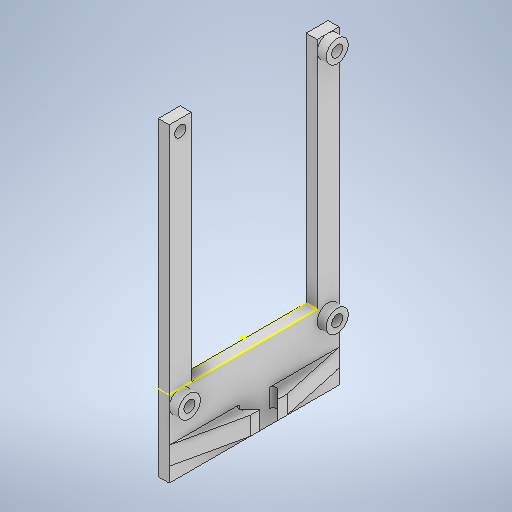
# Autodesk Inventor part: Support_pcb
Saved by Autodesk Inventor 2025 (Build 290162000, 162)
## iProperties
Created: 2026-10-27
Part Number: Support_pcb
Material: Generic
Document SubType Name: Modeling
Designer: diego
Density: 1 g/cm^3
Appearance: Default
Author: diego
Autodesk Inventor part; units mm, degrees
ref_plane "YZ Plane" through (0, 0, 0) normal (1, 0, 0) x (0, 1, 0)
ref_plane "XZ Plane" through (0, 0, 0) normal (0, 1, 0) x (-1, 0, 0)
ref_plane "XY Plane" through (0, 0, 0) normal (0, 0, 1) x (1, 0, 0)
sketch "Sketch1" plane through (0, 0, 0) normal (1, 0, 0) x (0, 1, 0)
  line L0 (-35, 23.25) -> (35, 23.25)
  line L1 (35, 23.25) -> (35, -23.25)
  line L2 (35, -23.25) -> (-35, -23.25)
  line L3 (-35, -23.25) -> (-35, 23.25)
  line L4 (-35, 23.25) -> (35, -23.25) construction
  line L5 (35, 23.25) -> (-35, -23.25) construction
  point P0 (0, 0)
  dimension "d0" = 70
  dimension "d1" = 46.5
  constraints: 12 end point, 2 midpoint, 2 parallel, 1 horizontal, 1 perpendicular
  measures "d0" distance of L1.end L2.end
  measures "d1" distance of L0.end L1.end
extrude "Extrusion1" add sketch "Sketch1" along normal blind 3
sketch "Sketch2" plane through (3, 0, 0) normal (1, 0, 0) x (0, 0, -1)
  line L0 (-20.25, -32) -> (20.25, -32)
  line L1 (20.25, -32) -> (20.25, 32)
  line L2 (20.25, 32) -> (-20.25, 32)
  line L3 (-20.25, 32) -> (-20.25, -32)
  line L4 (-20.25, -32) -> (20.25, 32) construction
  line L5 (20.25, -32) -> (-20.25, 32) construction
  circle A0 centre (-20.25, 32) radius 1.5
  circle A1 centre (20.25, 32) radius 1.5
  circle A2 centre (20.25, -32) radius 1.5
  circle A3 centre (-20.25, -32) radius 1.5
  point P0 (0, 0)
  dimension "d4" = 40.5
  dimension "d5" = 64
  dimension "d6" = 3
  dimension "d7" = 3
  dimension "d8" = 3
  dimension "d9" = 3
  constraints: 12 end point, 4 centre point, 4 coincident, 2 midpoint, 2 parallel, 1 horizontal, 1 perpendicular
  measures "d4" distance of L2.end L1.end
  measures "d5" distance of L1.end L0.end
  measures "d6" diameter of A0
  measures "d7" diameter of A1
  measures "d8" diameter of A2
  measures "d9" diameter of A3
extrude "Extrusion2" cut sketch "Sketch2" against normal blind 3 contours L3 A3 L0 | L0 A3 L3 | A2 L1 L0 | L0 L1 A2 | A0 L2 L3 | L3 L2 A0 | A1 L2 L1 | L1 L2 A1
sketch "Sketch3" plane through (3, 0, 0) normal (1, 0, 0) x (0, 0, -1)
  circle A0 centre (20.25, -32) radius 1.5 projected
  circle A1 centre (20.25, 32) radius 1.5 projected
  circle A2 centre (-20.25, -32) radius 1.5 projected
  circle A3 centre (-20.25, 32) radius 1.5 projected
  line L0 (23.25, -35) -> (23.25, 35) projected
  line L1 (23.25, 35) -> (-23.25, 35) projected
  line L2 (-23.25, 35) -> (-23.25, -35) projected
  line L3 (-23.25, -35) -> (23.25, -35) projected
  circle A4 centre (-20.25, 32) radius 3
  circle A5 centre (20.25, 32) radius 3
  circle A6 centre (-20.25, -32) radius 3
  circle A7 centre (20.25, -32) radius 3
  point P0 (0, 0)
  dimension "d12" = 1.5
  dimension "d13" = 1.5
  dimension "d14" = 1.5
  dimension "d15" = 1.5
  constraints: 4 centre point
  measures "d12" radial gap between concentric circles of A3 A4
  measures "d13" radial gap between concentric circles of A1 A5
  measures "d14" radial gap between concentric circles of A2 A6
  measures "d15" radial gap between concentric circles of A0 A7
extrude "Extrusion3" add sketch "Sketch3" along normal blind 2.5 contours A7 | A5 | A6 | A4
sketch "Sketch4" plane through (3, -35, -23.25) normal (1, 0, 0) x (0, 0, -1)
  line L0 (0, 0) -> (0, 3) projected
  line L1 (0, 70) -> (-3, 70) projected
  arc A0 (0, 67) -> (-3, 70) centre (-3, 67) ccw projected
  line L2 (-3, 70) -> (-43.5, 70) projected
  arc A1 (-46.5, 67) -> (-43.5, 70) centre (-43.5, 67) ccw projected
  line L3 (-43.5, 70) -> (-46.5, 70) projected
  line L4 (-46.5, 70) -> (-46.5, 67) projected
  line L5 (-46.5, 0) -> (-43.5, 0) projected
  arc A2 (-46.5, 3) -> (-43.5, 0) centre (-43.5, 3) ccw projected
  line L6 (-43.5, 0) -> (-3, 0) projected
  arc A3 (0, 3) -> (-3, 0) centre (-3, 3) ccw projected
  line L7 (-3, 0) -> (0, 0) projected
  line L8 (-40.5, 70) -> (-40.5, 0)
  circle A4 centre (-43.5, 67) radius 3 projected
  line L9 (-6, 70) -> (-6, 0)
  circle A5 centre (-3, 67) radius 3 projected
  line L10 (0, 3) -> (0, 67) projected
  arc A6 (-3, 70) -> (0, 67) centre (-3, 67) ccw projected
  line L11 (-46.5, 67) -> (-46.5, 3) projected
  arc A7 (-43.5, 0) -> (-46.5, 3) centre (-43.5, 3) ccw projected
  arc A8 (-3, 0) -> (0, 3) centre (-3, 3) ccw projected
  line L12 (-46.5, 3) -> (-46.5, 0) projected
  line L13 (0, 67) -> (0, 70) projected
  arc A9 (-43.5, 70) -> (-46.5, 67) centre (-43.5, 67) ccw projected
  line L14 (0, 6) -> (-46.5, 6)
  circle A10 centre (-3, 3) radius 3 projected
  point P0 (-23.25, 35)
  point P1 (-40.5, 6)
  point P2 (-6, 6)
  constraints: 6 end point, 6 point on line, 3 perpendicular, 2 vertical, 2 vertical alignment, 1 tangent
extrude "Extrusion4" cut sketch "Sketch4" against normal through all contours L14 L8 L2 L9
sketch "Sketch5" plane through (0, -35, -23.25) normal (0, -1, 0) x (1, 0, 0)
  line L0 (0, 46.5) -> (0, 0) projected
  line L1 (0, 0) -> (3, 0) projected
  line L2 (3, 3) -> (3, 0) projected
  line L3 (3, 43.5) -> (3, 3) projected
  line L4 (3, 46.5) -> (3, 43.5) projected
  line L5 (0, 46.5) -> (3, 46.5) projected
  point P0 (0, 23.25)
extrude "Extrusion5" add sketch "Sketch5" along normal blind 15
sketch "Sketch6" plane through (0, -50, -23.25) normal (0, -1, 0) x (1, 0, 0)
  line L0 (0, 46.5) -> (0, 0) projected
  line L1 (0, 0) -> (3, 0) projected
  line L2 (3, 0) -> (3, 46.5) projected
  line L3 (3, 46.5) -> (0, 46.5) projected
  line L4 (1.5, 46.5) -> (16.5, 23.25)
  line L5 (16.5, 23.25) -> (1.5, 0)
  line L6 (1.5, 0) -> (-13.5, 23.25)
  line L7 (-13.5, 23.25) -> (1.5, 46.5)
  line L8 (-13.5, 23.25) -> (16.5, 23.25)
  point P0 (0, 23.25)
  point P1 (1.5, 23.25)
  dimension "d24" = 15
  constraints: 10 end point, 3 midpoint, 2 parallel, 1 horizontal
  measures "d24" distance of L4.end point (1.5, 23.25)
extrude "Extrusion6" add sketch "Sketch6" against normal blind 3 contours L7 L4 L2 L8 L0 | L0 L8 L7 | L8 L2 L5 L6 L0 | L0 L6 L8 | L4 L8 L2 | L8 L5 L2
sketch "Sketch7" plane through (5.5, 32, 20.25) normal (1, 0, 0) x (0, 0, -1)
  circle A0 centre (0, 0) radius 3 projected
  circle A1 centre (0, 0) radius 1.5 projected
  point P0 (20.25, -32)
extrude "Extrusion7" cut sketch "Sketch7" against normal up to surface (2.5 mm away)
sketch "Sketch8" plane through (3, -32, 20.25) normal (1, 0, 0) x (0, 0, -1)
  circle A0 centre (0, 64) radius 1.5 projected
  line L0 (3, 67) -> (-3, 67) projected
  line L1 (-3, 67) -> (-3, 0) projected
  circle A1 centre (0, 0) radius 3 projected
  line L2 (-3, 0) -> (-3, -18) projected
  line L3 (-0.675, -18) -> (-3, -18) projected
  line L4 (-0.675, -18) -> (-0.675, -15) projected
  line L5 (-0.675, -15) -> (41.175, -15) projected
  line L6 (41.175, -15) -> (41.175, -18) projected
  line L7 (43.5, -18) -> (41.175, -18) projected
  line L8 (43.5, 0) -> (43.5, -18) projected
  circle A2 centre (40.5, 0) radius 3 projected
  line L9 (43.5, 0) -> (43.5, 64) projected
  arc A3 (37.5, 64) -> (43.5, 64) centre (40.5, 64) ccw projected
  line L10 (37.5, 64) -> (37.5, 3) projected
  line L11 (37.5, 3) -> (3, 3) projected
  line L12 (3, 3) -> (3, 67) projected
  line L13 (0, -3) -> (40.5, -3)
  circle A4 centre (0, 0) radius 3 projected
  line L14 (41.175, -18) -> (20.25, -18) projected
  line L15 (20.25, -18) -> (20.25, -3)
  line L16 (-0.675, -18) -> (20.25, -18) projected
  line L17 (12.25, -3) -> (15.25, -3)
  line L18 (15.25, -3) -> (15.25, -18)
  line L19 (15.25, -18) -> (12.25, -18)
  line L20 (12.25, -18) -> (12.25, -3)
  line L21 (25.25, -3) -> (25.25, -18)
  line L22 (28.25, -18) -> (28.25, -3)
  point P0 (20.25, 32)
  point P1 (28.25, -18)
  point P2 (28.25, -3)
  point P3 (25.25, -3)
  point P4 (25.25, -18)
  point P5 (15.25, -3)
  dimension "d27" = 3
  dimension "d28" = 5
  constraints: 16 end point, 4 symmetric about line, 2 parallel, 2 point on circle, 2 point on line, 2 tangent, 1 horizontal, 1 midpoint, 1 perpendicular
  measures "d27" distance between parallel lines of L18 L20
  measures "d28" distance between parallel lines of L21 L15
extrude "Extrusion8" add sketch "Sketch8" along normal blind 10 and the other way blind 13 contours L13 L18 L5 L20 | L5 L18 L16 L20 | L13 L22 L5 L21 | L5 L22 L14 L21
sketch "Sketch9" plane through (3, -47, -8) normal (0, 0, -1) x (-1, 0, 0)
  line L0 (-8.3387, 0) -> (-8.3387, -3) projected
  line L1 (0, 0) -> (-8.3387, 0) projected
  line L2 (0, 12) -> (0, 0) projected
  line L3 (-10, 12) -> (0, 12) projected
  line L4 (-10, -3) -> (-10, 12) projected
  line L5 (-8.3387, -3) -> (-10, -3) projected
  line L6 (-10, 0) -> (0, 0) projected
  line L7 (-10, 0) -> (0, 12)
  line L8 (3, 0) -> (3, 12) projected
  line L9 (11.3387, 0) -> (3, 0) projected
  line L10 (11.3387, -3) -> (11.3387, 0) projected
  line L11 (13, -3) -> (11.3387, -3) projected
  line L12 (13, 12) -> (13, -3) projected
  line L13 (3, 12) -> (13, 12) projected
  line L14 (13, 0) -> (3, 12)
  line L15 (3, 0) -> (13, 0) projected
  point P0 (3, 47)
  constraints: 4 end point, 2 point on line
extrude "Extrusion9" cut sketch "Sketch9" along normal through all both and the other way through all contours L4 L3 L7 | L13 L12 L14
sketch "Sketch10" plane through (3, -29, 17.25) normal (0, 1, 0) x (1, 0, 0)
  line L0 (-3, 0) -> (-3, 34.5) projected
  line L1 (0, 0) -> (-3, 0) projected
  line L2 (0, 34.5) -> (0, 0) projected
  line L3 (0, 34.5) -> (-3, 34.5) projected
  line L4 (0, 0) -> (-3, 0) projected
  line L5 (-3, 0) -> (-3, -6) projected
  line L6 (-3, -6) -> (0, -6) projected
  line L7 (0, 0) -> (0, -6) projected
  point P0 (-3, 17.25)
sketch "Sketch11" plane through (0, -47, -23.25) normal (0, 1, 0) x (1, 0, 0)
  line L0 (3, -15.25) -> (13, -15.25) projected
  line L1 (3, -18.25) -> (3, -15.25) projected
  line L2 (13, -18.25) -> (3, -18.25) projected
  line L3 (13, -17.825) -> (13, -18.25) projected
  line L4 (13, -15.25) -> (13, -17.825) projected
  line L5 (13, -31.25) -> (3, -31.25) projected
  line L6 (13, -28.675) -> (13, -31.25) projected
  line L7 (13, -28.25) -> (13, -28.675) projected
  line L8 (3, -28.25) -> (13, -28.25) projected
  line L9 (3, -31.25) -> (3, -28.25) projected
  line L10 (-10, -28.25) -> (0, -28.25) projected
  line L11 (-10, -28.675) -> (-10, -28.25) projected
  line L12 (-10, -31.25) -> (-10, -28.675) projected
  line L13 (0, -31.25) -> (-10, -31.25) projected
  line L14 (0, -28.25) -> (0, -31.25) projected
  line L15 (-10, -15.25) -> (0, -15.25) projected
  line L16 (-10, -17.825) -> (-10, -15.25) projected
  line L17 (-10, -18.25) -> (-10, -17.825) projected
  line L18 (0, -18.25) -> (-10, -18.25) projected
  line L19 (0, -15.25) -> (0, -18.25) projected
  point P0 (0, -23.25)
extrude "Extrusion10" cut sketch "Sketch11" along normal blind 14.7625
sketch "Sketch12" plane through (0, -50, -23.25) normal (0, -1, 0) x (1, 0, 0)
  line L0 (-8.3387, 15.25) -> (0, 2.325) projected
  line L1 (0, 2.325) -> (0, 0) projected
  line L2 (0, 0) -> (3, 0) projected
  line L3 (3, 0) -> (3, 2.325) projected
  line L4 (3, 2.325) -> (11.3387, 15.25) projected
  line L5 (11.3387, 15.25) -> (13, 15.25) projected
  line L6 (13, 17.825) -> (13, 15.25) projected
  line L7 (13, 17.825) -> (16.5, 23.25) projected
  line L8 (16.5, 23.25) -> (13, 28.675) projected
  line L9 (13, 31.25) -> (13, 28.675) projected
  line L10 (13, 31.25) -> (11.3387, 31.25) projected
  line L11 (11.3387, 31.25) -> (3, 44.175) projected
  line L12 (3, 44.175) -> (3, 46.5) projected
  line L13 (3, 46.5) -> (0, 46.5) projected
  line L14 (0, 46.5) -> (0, 44.175) projected
  line L15 (0, 44.175) -> (-8.3387, 31.25) projected
  line L16 (-8.3387, 31.25) -> (-10, 31.25) projected
  line L17 (-10, 28.675) -> (-10, 31.25) projected
  line L18 (-10, 28.675) -> (-13.5, 23.25) projected
  line L19 (-13.5, 23.25) -> (-10, 17.825) projected
  line L20 (-10, 15.25) -> (-10, 17.825) projected
  line L21 (-10, 15.25) -> (-8.3387, 15.25) projected
  line L22 (3, 44.175) -> (3, 2.325) projected
  line L23 (3, 0) -> (3, 2.325) projected
  line L24 (3, 6) -> (3, 0) projected
  line L25 (3, 0) -> (3, 6) projected
  line L26 (3, 6) -> (3, 40.5) projected
  line L27 (3, 40.5) -> (3, 46.5) projected
  line L28 (3, 46.5) -> (3, 40.5) projected
  line L29 (3, 44.175) -> (3, 46.5) projected
  line L30 (3, 42) -> (3, 45) projected
  line L31 (3, 6) -> (3, 40.5) projected
  line L32 (0, 2.325) -> (0, 44.175) projected
  line L33 (0, 46.5) -> (0, 44.175) projected
  line L34 (0, 40.5) -> (0, 46.5) projected
  line L35 (0, 40.5) -> (0, 6) projected
  line L36 (0, 0) -> (0, 6) projected
  line L37 (0, 2.325) -> (0, 0) projected
  line L38 (0, 42) -> (0, 45) projected
  line L39 (0, 42) -> (0, 45) projected
  line L40 (0, 1.5) -> (0, 4.5) projected
  line L41 (0, 1.5) -> (0, 4.5) projected
  point P0 (0, 23.25)
extrude "Extrusion11" cut sketch "Sketch12" against normal blind 10 contours L21 L20 L19 L18 L17 L16 L15 L32 L0 | L22 L11 L10 L9 L8 L7 L6 L5 L4
sketch "Sketch13" plane through (3, -32, -20.25) normal (1, 0, 0) x (0, 0, -1)
  circle A0 centre (-40.5, 64) radius 1.5 projected
  line L0 (3, -18) -> (-43.5, -18) projected
  line L1 (3, 0) -> (3, -18) projected
  circle A1 centre (0, 0) radius 3 projected
  line L2 (3, 0) -> (3, 64) projected
  arc A2 (-3, 64) -> (3, 64) centre (0, 64) ccw projected
  line L3 (-3, 64) -> (-3, 3) projected
  line L4 (-3, 3) -> (-37.5, 3) projected
  line L5 (-37.5, 3) -> (-37.5, 67) projected
  line L6 (-37.5, 67) -> (-43.5, 67) projected
  line L7 (-43.5, 67) -> (-43.5, 0) projected
  circle A3 centre (-40.5, 0) radius 3 projected
  line L8 (-43.5, 0) -> (-43.5, -18) projected
  line L9 (-40.5, -3) -> (0, -3)
  line L10 (-20.25, -3) -> (-20.25, -18) construction
  circle A4 centre (-40.5, 0) radius 3 projected
  line L11 (-25.25, -14) -> (-15.25, -14)
  line L12 (-15.25, -14) -> (-15.25, -9)
  line L13 (-15.25, -9) -> (-25.25, -9)
  line L14 (-25.25, -9) -> (-25.25, -14)
  line L15 (-25.25, -14) -> (-15.25, -9) construction
  line L16 (-15.25, -14) -> (-25.25, -9) construction
  point P0 (-20.25, 32)
  point P1 (-20.25, -11.5)
  dimension "d39" = 10
  dimension "d40" = 5
  dimension "d41" = 6
  constraints: 16 end point, 4 midpoint, 2 horizontal, 2 parallel, 2 point on circle, 1 perpendicular, 1 point on line, 1 tangent
  measures "d39" distance of L13.end L12.end
  measures "d40" distance of L12.end L11.end
  measures "d41" distance between parallel lines of L13 L9
extrude "Extrusion12" add sketch "Sketch13" along normal blind 4 contours L14 L13 L12 L11
sketch "Sketch14" plane through (3, -41, 5) normal (0, 1, 0) x (1, 0, 0)
  line L0 (0, 0) -> (0, 10) projected
  line L1 (0, 0) -> (4, 0) projected
  line L2 (4, 10) -> (4, 0) projected
  line L3 (0, 10) -> (4, 10) projected
  line L4 (-3, -18.25) -> (-3, 28.25) projected
  line L5 (0, 10) -> (0, 0) projected
  line L6 (0, 0) -> (0, 10) projected
  line L7 (0, -16.75) -> (0, -13.75) projected
  line L8 (0, 28.25) -> (0, -18.25) projected
  line L9 (0, 28.25) -> (0, 22.25) projected
  line L10 (0, 28.25) -> (0, 22.25) projected
  line L11 (0, 22.25) -> (0, -12.25) projected
  line L12 (0, -12.25) -> (0, -18.25) projected
  line L13 (0, -12.25) -> (0, -18.25) projected
  line L14 (0, 28.25) -> (0, -18.25) projected
  line L15 (4, 10) -> (4, 0) projected
  line L16 (0, -18.25) -> (4, 0)
  line L17 (4, 0) -> (4, 10)
  line L18 (0, 28.25) -> (4, 10)
  point P0 (-3, 5)
  point P1 (0, -13.75)
  point P2 (0, -16.75)
  constraints: 6 end point, 1 vertical, 1 other
extrude "Extrusion13" add sketch "Sketch14" against normal blind 5 contours L1 L16 L8 L7 | L8 L18 L3
sketch "Sketch15" plane through (3, -41, 23.25) normal (0, 1, 0) x (1, 0, 0)
  line L0 (0, 0) -> (0, 46.5) projected
  line L1 (0, 0) -> (4, 18.25) projected
  line L2 (4, 28.25) -> (4, 18.25) projected
  line L3 (4, 28.25) -> (0, 46.5) projected
  line L4 (4, 18.25) -> (7.2426, 18.25) construction
  line L5 (0, 40.5) -> (0, 6) projected
  line L6 (0, 16.6642) -> (0, 29.8358)
  line L7 (0, 23.25) -> (4, 23.25) construction
  line L8 (4, 20.75) -> (4, 25.75)
  line L9 (4, 28.25) -> (4, 18.25) projected
  line L10 (4, 20.75) -> (1.7071, 18.4571)
  line L11 (4, 20.75) -> (7.2426, 20.75) construction
  line L12 (4, 25.75) -> (1.7071, 28.0429)
  line L13 (0, 46.5) -> (0, 0) projected
  line L14 (4, 25.75) -> (7.2426, 25.75) construction
  line L15 (0, 19.1642) -> (0, 27.3358)
  arc A0 (0, 19.1642) -> (1.7071, 18.4571) centre (1, 19.1642) ccw
  arc A1 (1.7071, 28.0429) -> (0, 27.3358) centre (1, 27.3358) ccw
  point P0 (-3, 23.25)
  point P1 (0, 14.25)
  point P2 (0, 32.25)
  point P3 (0, 16.75)
  point P4 (0, 29.75)
  dimension "d49" = 5
  dimension "d50" = 135
  dimension "d51" = 135
  dimension "d52" = 1
  constraints: 18 end point, 10 point on line, 5 midpoint, 4 horizontal, 4 point on circle, 4 tangent, 2 centre point, 2 equal length, 2 vertical, 1 collinear, 1 equal radius, 2 other
  measures "d49" distance of L8.start L8.end
  measures "d50" angle of L10 L11
  measures "d51" angle of L14 L12
  measures "d52" radius of A0
extrude "Extrusion14" cut sketch "Sketch15" against normal blind 5 contours L10 A0 L0 A1 L12 L2
body "Solid1"
